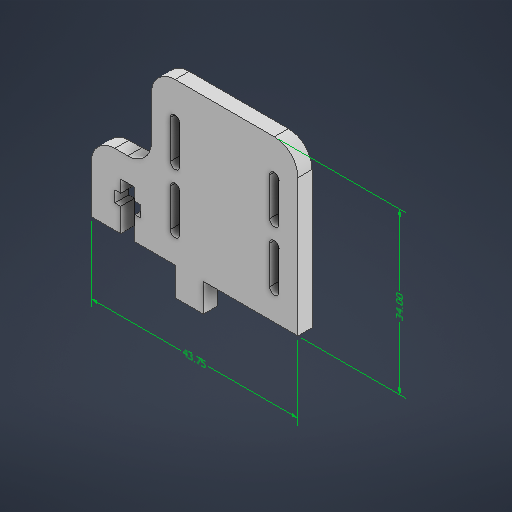
# Autodesk Inventor part: Camera_holder
Saved by Autodesk Inventor 2026 (Build 300175050, 175E)
## iProperties
Created: 2026-08-19
Part Number: Camera_holder
Material: Generic
Document SubType Name: Modeling
Designer: nose
Density: 1 g/cm^3
Appearance: Default
Mass: 3.41761 g
Surface Area: 30.9005 cm^2
Volume: 3.41761 cm^3
Author: nose
Autodesk Inventor part; units mm, degrees
ref_plane "YZ Plane" through (0, 0, 0) normal (1, 0, 0) x (0, 1, 0)
ref_plane "XZ Plane" through (0, 0, 0) normal (0, 1, 0) x (-1, 0, 0)
ref_plane "XY Plane" through (0, 0, 0) normal (0, 0, 1) x (1, 0, 0)
sketch "Sketch1" plane through (0, 0, 0) normal (0, 0, 1) x (1, 0, 0)
  line L0 (15.5, 17) -> (-15.5, 17)
  line L1 (-15.5, 17) -> (-15.5, -17)
  line L2 (-15.5, -17) -> (15.5, -17)
  line L3 (15.5, -17) -> (15.5, 17)
  line L4 (15.5, 17) -> (-15.5, -17) construction
  line L5 (-15.5, 17) -> (15.5, -17) construction
  circle A0 centre (-10.5, 5.5) radius 1
  circle A1 centre (10.5, 5.5) radius 1
  circle A2 centre (10.5, -7) radius 1
  circle A3 centre (-10.5, -7) radius 1
  line L6 (-10.5, -11) -> (-10.5, -3) construction
  line L7 (-9.5, -11) -> (-9.5, -3)
  line L8 (-11.5, -3) -> (-11.5, -11)
  arc A4 (-11.5, -11) -> (-9.5, -11) centre (-10.5, -11) ccw
  arc A5 (-9.5, -3) -> (-11.5, -3) centre (-10.5, -3) ccw
  circle A6 centre (10.5, -7) radius 1
  line L9 (10.5, -11) -> (10.5, -3) construction
  line L10 (11.5, -11) -> (11.5, -3)
  line L11 (9.5, -3) -> (9.5, -11)
  arc A7 (9.5, -11) -> (11.5, -11) centre (10.5, -11) ccw
  arc A8 (11.5, -3) -> (9.5, -3) centre (10.5, -3) ccw
  circle A9 centre (-10.5, 5.5) radius 1
  line L12 (-10.5, 1.5) -> (-10.5, 9.5) construction
  line L13 (-9.5, 1.5) -> (-9.5, 9.5)
  line L14 (-11.5, 9.5) -> (-11.5, 1.5)
  arc A10 (-11.5, 1.5) -> (-9.5, 1.5) centre (-10.5, 1.5) ccw
  arc A11 (-9.5, 9.5) -> (-11.5, 9.5) centre (-10.5, 9.5) ccw
  circle A12 centre (10.5, 5.5) radius 1
  line L15 (10.5, 1.5) -> (10.5, 9.5) construction
  line L16 (11.5, 1.5) -> (11.5, 9.5)
  line L17 (9.5, 9.5) -> (9.5, 1.5)
  arc A13 (9.5, 1.5) -> (11.5, 1.5) centre (10.5, 1.5) ccw
  arc A14 (11.5, 9.5) -> (9.5, 9.5) centre (10.5, 9.5) ccw
  point P0 (0, 0)
  dimension "d0" = 31
  dimension "d1" = 34
  dimension "d5" = 2
  dimension "d32" = 2
  dimension "d33" = 2
  dimension "d35" = 2
  dimension "d37" = 21
  dimension "d38" = 12.5
  dimension "d41" = 10
  dimension "d42" = 5
  dimension "d43" = 2
  dimension "d44" = 8
  dimension "d45" = 2
  dimension "d46" = 2
  dimension "d47" = 8
  dimension "d49" = 2
  dimension "d50" = 2
  dimension "d51" = 8
  dimension "d53" = 2
  dimension "d54" = 2
  dimension "d55" = 8
  constraints: 44 end point, 16 point on circle, 16 tangent, 15 centre point, 6 midpoint, 6 parallel, 4 vertical, 3 coincident, 2 horizontal alignment, 2 vertical alignment, 1 horizontal, 1 perpendicular
  measures "d0" distance of L0.start L0.end
  measures "d1" distance of L0.end L1.end
  measures "d5" diameter of A0
  measures "d32" diameter of A1
  measures "d33" diameter of A2
  measures "d35" diameter of A3
  measures "d37" distance of A1.centre A0.centre
  measures "d38" distance of A3.centre A0.centre
  measures "d41" distance from line of L2 A3.centre
  measures "d42" distance from line of L1 A3.centre
  measures "d43" diameter of A5
  measures "d44" distance of L8.start L8.end
  measures "d45" diameter of A6
  measures "d46" diameter of A8
  measures "d47" distance of L11.start L11.end
  measures "d49" diameter of A9
  measures "d50" diameter of A11
  measures "d51" distance of L14.start L14.end
  measures "d53" diameter of A12
  measures "d54" diameter of A14
  measures "d55" distance of L17.start L17.end
extrude "Picam_holder" add sketch "Sketch1" along normal blind 3
sketch "Sketch2" plane through (0, 0, 0) normal (0, 0, 1) x (1, 0, 0)
  line L0 (-15.5, -17) -> (15.5, -17) projected
  line L1 (-20.5, 2.3881) -> (-20.5, -26.4725)
  line L2 (-23.25, -12) -> (-17.75, -12)
  line L3 (-17.75, -12) -> (-17.75, -9.6)
  line L4 (-17.75, -9.6) -> (-23.25, -9.6)
  line L5 (-23.25, -9.6) -> (-23.25, -12)
  line L6 (-23.25, -12) -> (-17.75, -9.6) construction
  line L7 (-17.75, -12) -> (-23.25, -9.6) construction
  line L8 (-22, -7) -> (-19, -7)
  line L9 (-19, -7) -> (-19, -17)
  line L10 (-19, -17) -> (-22, -17)
  line L11 (-22, -17) -> (-22, -7)
  line L12 (-22, -7) -> (-19, -17) construction
  line L13 (-19, -7) -> (-22, -17) construction
  line L14 (-7.5, 4.2998) -> (-7.5, -26.238)
  line L15 (-10.5, -23) -> (-4.5, -23)
  line L16 (-4.5, -23) -> (-4.5, -17)
  line L17 (-4.5, -17) -> (-10.5, -17)
  line L18 (-10.5, -17) -> (-10.5, -23)
  line L19 (-10.5, -23) -> (-4.5, -17) construction
  line L20 (-4.5, -23) -> (-10.5, -17) construction
  line L21 (0, 21.8255) -> (0, -24.6051)
  line L22 (-15.5, -17) -> (-28.25, -17)
  line L23 (-28.25, -17) -> (-28.25, -2)
  line L24 (-28.25, -2) -> (-15.5, -2)
  line L25 (-15.5, -2) -> (-15.5, -17)
  point P0 (0, 0)
  point P1 (-20.5, -10.8)
  point P2 (-20.5, -12)
  point P3 (-7.5, -20)
  point P4 (-19, -12)
  point P5 (-22, -12)
  point P6 (-22, -9.6)
  point P7 (-19, -9.6)
  point P8 (-4.5, -17)
  point P9 (-10.5, -17)
  point P10 (-15.5, -9.6)
  point P11 (-15.5, -12)
  dimension "d17" = 5.5
  dimension "d18" = 2.4
  dimension "d19" = 10
  dimension "d20" = 3
  dimension "d22" = 5
  dimension "d23" = 6
  dimension "d24" = 6
  dimension "d26" = 7.5
  dimension "d27" = 15
  dimension "d64" = 10
  dimension "d65" = 5
  constraints: 50 end point, 8 parallel, 6 midpoint, 4 horizontal, 4 perpendicular, 4 point on line, 4 vertical, 1 collinear
  measures "d17" distance of L3.end L4.end
  measures "d18" distance of L2.end L3.end
  measures "d19" distance of L8.end L9.end
  measures "d20" distance between parallel lines of L9 L11
  measures "d22" distance between parallel lines of L0 L2
  measures "d23" distance of L15.end L16.end
  measures "d24" distance of L15.start L15.end
  measures "d26" distance between parallel lines of L14 L21
  measures "d27" distance of L22.end L23.end
  measures "d64" distance between parallel lines of L18 L1
  measures "d65" distance between parallel lines of L23 L5
extrude "Screw" add sketch "Sketch2" along normal blind 3 contours L0 L14 L15 L18 | L22 L9 L2 L3 L4 L8 L1 L24 L25 | L0 L16 L15 L14 | L1 L8 L11 L4 L5 L2 L22 L23 L24
fillet "Fillet1" radius 5 4 edges at (-28.25, -2, 1.5) (-15.5, -2, 1.5) (-15.5, 17, 1.5) (15.5, 17, 1.5)
equation "\"d1\" = Picam_holder_offset + Picam_length + Camera_y_offset"
equation "\"d5\" = Picam_hole_dia"
equation "\"d32\" = Picam_hole_dia"
equation "\"d33\" = Picam_hole_dia"
equation "\"d35\" = Picam_hole_dia"
equation "\"d37\" = Picam_hole_x_dist"
equation "\"d38\" = Picam_hole_y_dist"
equation "\"d42\" = Picam_holder_offset"
equation "\"d43\" = Picam_hole_dia"
equation "\"d45\" = d48"
equation "\"d46\" = d48"
equation "\"d49\" = d52"
equation "\"d50\" = d52"
equation "\"d53\" = d56"
equation "\"d54\" = d56"
equation "\"d17\" = Nut_width"
equation "\"d18\" = Nut_thickness"
equation "\"d19\" = Screw_length"
equation "\"d20\" = Screw_dia"
equation "\"d23\" = Pin_width"
equation "\"d24\" = Pin_width"
equation "\"Picam_width\" = 25"
equation "\"Picam_length\" = 24"
equation "\"Picam_holder_offset\" = 5"
equation "\"Picam_hole_dia\" = 2"
equation "\"Pin_width\" = 6"
equation "\"Nut_width\" = 5.5"
equation "\"Nut_thickness\" = 2.4"
equation "\"Screw_dia\" = 3"
equation "\"Screw_length\" = 10"
equation "\"Camera_x_offset\" = 7.5"
equation "\"Picam_hole_x_dist\" = 21"
equation "\"Picam_hole_y_dist\" = 12.5"
equation "\"Camera_y_offset\" = 5"
equation "\"d48\" = 2"
equation "\"d52\" = 2"
equation "\"d56\" = 2"
equation "\"Picam_hole_slot\" = 8"
body "Solid1"
